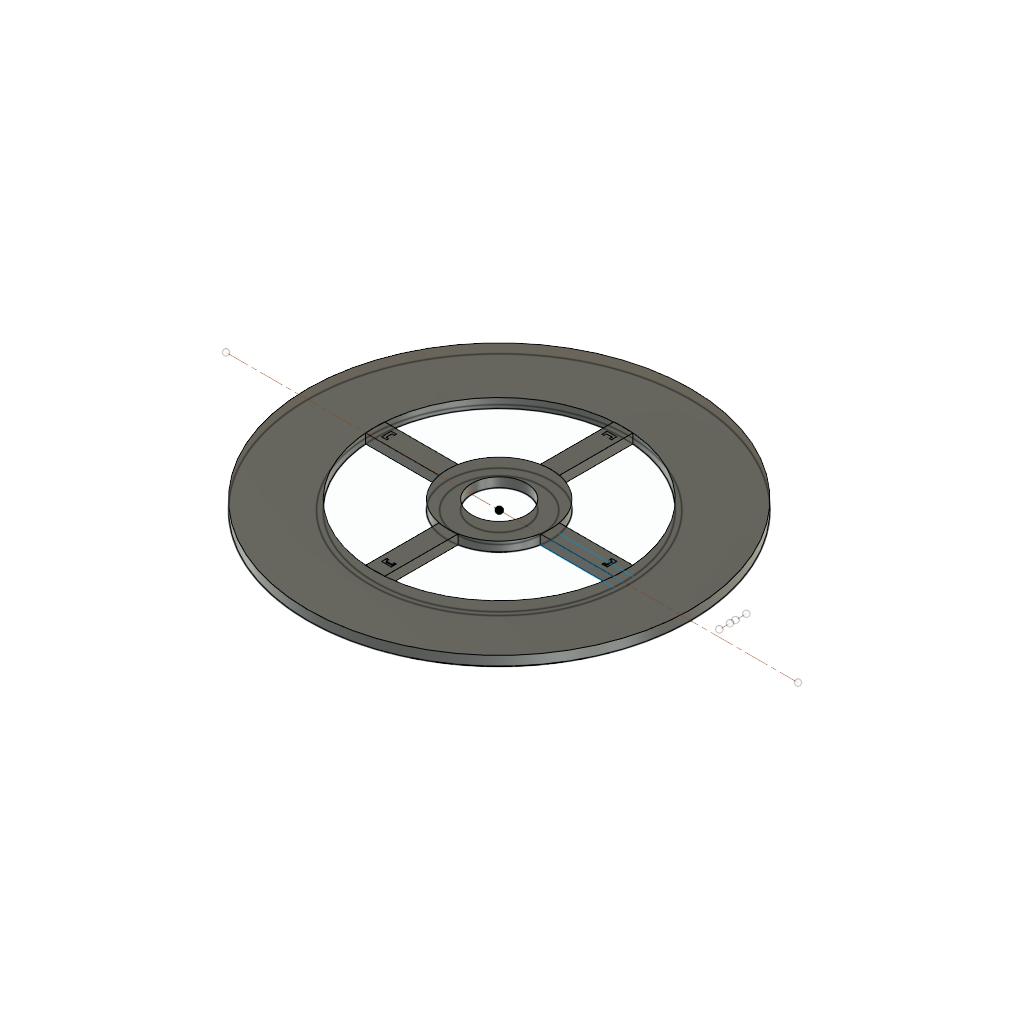
Mood Lamp (Autodesk Fusion 360 design; units mm, degrees)
Autodesk Fusion 360 part; units mm, degrees
other "Base Mesh Feature1"
sketch "Sketch1" plane through (0, 0, 0) normal (0, 0, 1) x (1, 0, 0)
  circle A0 centre (0, 0) radius 14.25
  circle A1 centre (0, 0) radius 22
  circle A2 centre (0, 0) radius 26.9
  circle A3 centre (0, 0) radius 67.45
  circle A4 centre (0, 0) radius 100
  line L0 (-142.6746, 0) -> (156.0338, 0)
  circle A5 centre (0, 0) radius 65
  line L1 (111.4082, 17.6441) -> (111.4082, 11.9728) construction
  line L2 (111.4082, 9.0712) -> (111.4082, 3.5318) construction
  line L3 (26.9, 0) -> (65, 0)
  line L4 (26.4312, 5) -> (64.8074, 5)
  line L5 (26.4312, -5) -> (64.8074, -5)
  dimension "d1" = 28.5
  dimension "d2" = 44
  dimension "d3" = 53.8
  dimension "d4" = 134.9
  dimension "d5" = 200
  dimension "d34" = 130
  dimension "d39" = 10
  dimension "d40" = 5
  constraint coincident A0.centre A1.centre
  constraint concentric A0 A4
  constraint horizontal L0
  constraint concentric A0 A5
  constraint vertical L1
  constraint vertical L2
  constraint coincident L0 L3.end
  constraint coincident A5 L3.end
  constraint coincident A2 L3.start
  constraint coincident A2 L4.start
  constraint coincident A5 L4.end
  constraint horizontal L4
  constraint coincident A2 L5.start
  constraint coincident A5 L5.end
  constraint parallel L4 L5
  measures "d1" diameter of A0
  measures "d2" diameter of A1
  measures "d3" diameter of A2
  measures "d4" diameter of A3
  measures "d5" diameter of A4
  measures "d34" diameter of A5
  measures "d39" distance of L4 L5
  measures "d40" distance of L3 L5
extrude "Extrude7" add sketch "Sketch1" along normal blind 5 contours A0 A1 L0 | A0 A1 L0 | A1 A2 L0 | A1 A2 L0 makes body 1
extrude "Extrude8" add sketch "Sketch1" along normal blind 5 separate body contours A3 L0 A5 | A3 L0 A5 | A3 A4 L0 | A3 A4 L0 makes body 2
sketch "Sketch6" plane through (0, 0, 0) normal (0, 0, 1) x (1, 0, 0)
  circle A0 centre (0, 0) radius 14.25 construction
  circle A1 centre (0, 0) radius 26.9 construction
  circle A2 centre (0, 0) radius 65 construction
  circle A3 centre (0, 0) radius 100
extrude "Extrude9" add sketch "Sketch1" along normal blind 5 separate body contours A2 L0 A5 L3 L5 | A2 L0 A5 L3 L4 makes body 3
extrude "Extrude10" add sketch "Sketch1" along normal blind 135 from surface at 5 separate body contours A3 A4 L0 | A3 A4 L0 makes body 4
sketch "Sketch10" plane through (0, 0, 140) normal (0, 0, 1) x (-1, 0, 0)
  circle A0 centre (0, 0) radius 67.45
  circle A1 centre (0, 0) radius 100
  line L0 (-161.3463, 0) -> (106.9998, 0)
  line L1 (-67.45, 0) -> (-100, 0)
  constraint horizontal L0
  constraint coincident A0 L1.start
  constraint coincident L0 L1.start
  constraint coincident A1 L1.end
  constraint coincident L0 L1.end
extrude "Extrude13" cut sketch "Sketch10" against normal up to surface (135 mm away) thin wall 1.5 centred open curves L1 bodies 4
pattern_circular "C-Pattern3" count 80 over 360 about axis through (0, 0, 1.75) along (0, 0, 1) of "Extrude13"
sketch "Sketch11" plane through (0, 5, 0) normal (0, 1, 0) x (-1, 0, 0)
  line L0 (-64.8074, 0) -> (-26.4312, 0)
  line L1 (-26.4312, 0) -> (-26.4312, 5)
  line L2 (-26.4312, 5) -> (-64.8074, 5)
  line L3 (-64.8074, 5) -> (-64.8074, 0)
  line L4 (-64.8074, 0) -> (-65, 0)
  line L5 (-64.8074, 5) -> (-65, 5)
  line L6 (-26.4312, 0) -> (-64.8074, 0)
  line L7 (-26.4312, 5) -> (-64.8074, 5)
  line L8 (-26.4312, 0) -> (-26.4312, 5)
  line L9 (-65, 0) -> (-65, 5)
  line L10 (-54.8074, 13.4675) -> (-54.8074, -3.2026) construction
  line L11 (-57.4074, 4.6) -> (-56.0074, 4.6)
  line L12 (-56.0074, 4.6) -> (-56.0074, 3.2)
  line L13 (-57.5074, 4.7) -> (-57.5074, 4.8)
  line L14 (-57.4074, 4.6) -> (-57.5074, 4.7)
  line L15 (-58.8574, 5) -> (-58.8574, 3.9)
  line L16 (-56.0074, 3.2) -> (-58.1574, 3.2)
  line L17 (-24.0318, 5) -> (-54.8074, 5) construction
  line L18 (-58.8574, 5) -> (-67.5419, 5) construction
  line L19 (-57.5074, 5) -> (-57.5074, 4.8)
  line L20 (-58.1574, 3.2) -> (-58.8574, 3.9)
  line L21 (-57.5074, 5) -> (-58.8574, 5)
  point P0 (-57.5074, 4.6)
  point P1 (-57.5074, 5)
  point P2 (-58.8574, 3.2)
  dimension "d73" = 10
  dimension "d76" = 1.2
  dimension "d81" = 0.1
  dimension "d82" = 0.1
  dimension "d85" = 0.2
  dimension "d88" = 1.4
  dimension "d90" = 1.35
  dimension "d92" = 1.8
  dimension "d93" = 0.7
  dimension "d94" = 0.7
  dimension "d95" = 2.15
  dimension "d96" = 0.4
  constraint perpendicular L8 L17
  constraint perpendicular L10 L17
  constraint coincident L1.end L17
  constraint perpendicular L11 L12
  constraint coincident P1 L17
  constraint vertical L13
  constraint coincident L11 P0
  constraint coincident P0 L13
  constraint coincident P1 L13
  constraint coincident L15.start L17
  constraint perpendicular L7 L15
  constraint coincident L7 L17.end
  constraint coincident L10 L17.end
  constraint collinear L17 L18
  constraint coincident P1 L19.start
  constraint coincident P2 L16
  constraint coincident P2 L15
  measures "d73" distance of L2.end L10
  measures "d76" distance of L10 L12
  measures "d81" distance of P0 L11.start
  measures "d82" distance of P0 L13.start
  measures "d85" distance of P1 L13.end
  measures "d88" distance of L11.end L11.start
  measures "d90" distance of L13 L15
  measures "d92" distance of L15.start P2
  measures "d93" distance of P2 L16.end
  measures "d94" distance of P2 L15.end
  measures "d95" distance of L12.end L16.end
  measures "d96" distance of L7 L11
extrude "Extrude15" add sketch "Sketch11" along normal mid plane 5 from surface at -5 separate body contours L2 L7 L11 L12 L13 L14 L15 L16 L19 L20 L21 makes body 5
fillet "Fillet1" radius 0.2 2 edges at (56.0074, 0, 4.6) (56.0074, 0, 3.2) on bodies 5
combine "Combine1" operation cut target body 3 tool bodies 5
sketch "Sketch12" plane through (0, 0, 5) normal (0, 0, 1) x (-1, 0, 0)
  line L0 (-57.5074, -2.5) -> (-58.8574, -2.5)
  line L1 (-58.8574, -2.5) -> (-58.8574, 2.5)
  line L2 (-58.8574, 2.5) -> (-57.5074, 2.5)
  line L3 (-57.5074, 2.5) -> (-57.5074, -2.5)
  arc A0 (-26.4312, 5) -> (-26.4312, -5) centre (0, 0) ccw
  line L4 (-26.4312, 5) -> (-64.8074, 5)
  arc A1 (-64.8074, 5) -> (-64.8074, -5) centre (0, 0) ccw
  line L5 (-64.8074, -5) -> (-26.4312, -5)
  line L6 (-57.5074, -2.5) -> (-56.1874, -2.5)
  line L7 (-56.1874, 2.5) -> (-57.5074, 2.5)
  line L8 (-57.5074, -1.5) -> (-56.0314, -1.5)
  line L9 (-56.0314, 1.5) -> (-57.5074, 1.5)
  line L10 (-57.5074, 1.5) -> (-57.5074, -1.5)
  line L11 (-56.0314, -1.5) -> (-56.1874, -1.5)
  line L12 (-56.0314, 1.5) -> (-56.1874, 1.5)
  line L13 (-57.5074, 2.5) -> (-57.5074, 1.5)
  line L14 (-57.5074, -1.5) -> (-57.5074, -2.5)
  line L15 (-56.1874, -2.5) -> (-56.1874, -1.5)
  line L16 (-56.1874, 1.5) -> (-56.1874, 2.5)
  dimension "d104" = 1
  dimension "d105" = 1.32
  dimension "d108" = 2.67
  constraint horizontal L6
  constraint vertical L15
  constraint horizontal L7
  constraint vertical L13
  constraint coincident L0.start L3.end
  constraint horizontal L8
  constraint horizontal L9
  constraint vertical L10
  constraint coincident L3 L8.start
  constraint perpendicular L11 L15
  constraint coincident L12.end L15
  constraint perpendicular L12 L15
  constraint collinear L13 L14
  constraint collinear L15 L16
  constraint equal L15 L16
  constraint coincident L2.end L3.start
  measures "d104" distance of L6.end L11.end
  measures "d105" distance of L14 L15
  measures "d108" distance of L0.end L15
extrude "Extrude16" cut sketch "Sketch12" against normal blind 0.5 contours L3 L6 L8 L14 L15 | L3 L7 L9 L13 L16 bodies 3
pattern_circular "C-Pattern5" count 4 over 360 about axis through (0, 0, 1.75) along (0, 0, 1) of bodies 3 makes body 6 at (0.556, 39.5581, 0) makes body 7 at (-39.5581, 0.556, 0) makes body 8 at (-0.556, -39.5581, 0)
pattern_circular "C-Pattern4" count 4 over 360 about axis through (0, 0, 1.75) along (0, 0, 1) of "Extrude9" makes body 9 at (-1.1145, 39.5755, 0) makes body 10 at (-39.5755, -1.1145, 0) makes body 11 at (1.1145, -39.5755, 0)
hidden bodies 4 11
equation "d82 = d81"
equation "d94 = d93"
